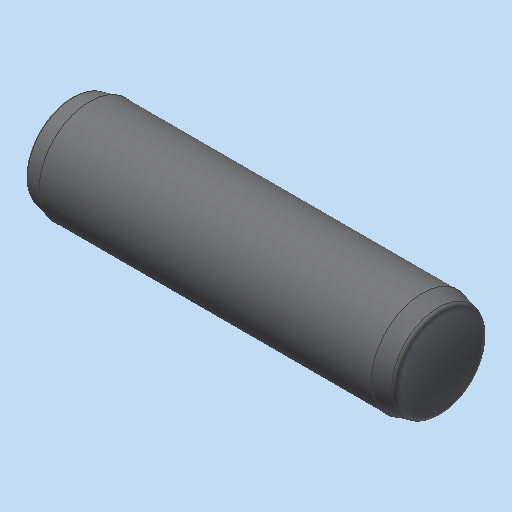
# Autodesk Inventor part: Zylinderstift_DIN_EN_ISO_8734___6x22
Saved by Autodesk Inventor 2023.3 (Build 273359000, 359)
## iProperties
Shininess: 64.0
Length Units: 11269
Angle Units: 11279
Time Units: 11290
Mass Units: 11283
Length Display Precision: 3
Angle Display Precision: 2
Compacted: True
Part Number: Zylinderstift_DIN_EN_ISO_8734___6x22
Document SubType Name: Modeling
Created: 2004-04-23
Description: =<RBPARTNOTITLE2>
Vendor: NORM8
Designer: C.Fischer
Manufacturer: Standard
Standards Organization: Custom
Density: 7.85 g/cm^3
Material: xStahl_AnP_Dummymaterial
Appearance: Stahl - normal AnP
Mass: 4.7383 g
Surface Area: 4.56133 cm^2
Volume: 0.603605 cm^3
DOC_ID: 5 F45 Zylinderstift_DIN_EN_ISO_8734___6x22
Control State: 0
Master: False
Checked Out: False
CNS_NB: Zylinderstift DIN EN ISO 8734 - 6x22
CNS_NN: DIN EN ISO 8734
CNS_NT: Zylinderstifte, aus gehaertetem Stahl und martensitischem nichtrostendem Stahl
CNS_NBSYN: Zylinderstift DIN EN ISO 8734 - $NENN.
CNS_LINA: Zylinderstift DIN EN ISO 8734 - 6x22
CNS_D: 6.000
CNS_L: 22.000
CNS_A: 1.200
CNS_NENN: 6x22
CNS_KT: DUMMY
PSOL_IDENT_0: {C:\partsolutions\data\23d-libs\bosch_bamberg\stifte\scherstifte\din_en_iso_8734.prj},164 {VTYP=3D},
PSOL_IDENT_1: {NB=Zylinderstift DIN EN ISO 8734 - 6x22},{NN=DIN EN ISO 8734},{DATE=26.11.2003},{GEOMDATE=26.11.200
PSOL_IDENT_2: 3},{VERSION=v1},{LINEID=790},{LINESUBID=-1},{WBVAR=}  {NB=Zylinderstift DIN EN ISO 8734 - 6x22},{LIN
PSOL_IDENT_3: A=Zylinderstift DIN EN ISO 8734 - 6x22},{KT=DUMMY},{IDNR=},{D=6.000},{L=22.000},{A=1.200},{NENN=6x22
PSOL_IDENT_4: }
DEF_STKID: T19045
Bezeichnung1: Zylinderstift DIN EN ISO 8734 - 6x22
Bezeichnung2: Zylinderstifte, aus gehaertetem Stahl u
RBPARTNOTITLE1: Parallel pins of hardened and martensitic stainless steel
RBPARTNOTITLE2: Zylinderstifte, aus gehaertetem Stahl und martensitischem nichtrostendem Stahl
RBDRAWINGMISSINGSPEC: --
AnP_Kategorie: 5
RBPARTMADEOF: ISO 8734 - 6x22 - A - St
Density: 0.0
Volumn: 0.0
Area: 0.0
PropertySet Name: Model Information
Title: Zylinderstift DIN EN ISO 8734 - 6x22
Author: C.Fischer
Keywords: =<RBPARTMADEOF>
Comments: =<RBSURFACE2>
Revision Number: 01
Autodesk Inventor part; units mm, degrees
sketch "Sketch_1" plane through (0, 0, 0) normal (0, 0, 1) x (1, 0, 0)
  line L0 (22, 0) -> (0, 0)
  arc A0 (0.48, 0) -> (0.0846, 2.4378) centre (-7.2331, 0) ccw
  arc A1 (0.2502, 2.7455) -> (0.0846, 2.4378) centre (0.3123, 2.5137) ccw
  line L1 (0.2502, 2.7455) -> (1.2, 3)
  line L2 (1.2, 3) -> (20.8, 3)
  line L3 (20.8, 3) -> (21.7498, 2.7455)
  arc A2 (21.9154, 2.4378) -> (21.7498, 2.7455) centre (21.6877, 2.5137) ccw
  arc A3 (21.9154, 2.4378) -> (21.52, 0) centre (29.2331, 0) ccw
  line L4 (21.52, 0) -> (0.48, 0)
  constraints: 10 end point, 8 point on circle, 4 centre point
revolve "Revolution1" add sketch "Sketch_1" angle 360 about axis through (22, 0, 0) along (1, 0, 0)
ref_plane "IP2_XY" through (0, 0, 0) normal (1, 0, 0) x (0, 0, -1)
ref_plane "IP2_YZ" through (0, 0, 0) normal (0, 0, -1) x (0, 1, 0)
ref_plane "IP1_XY" through (11, 0, 0) normal (1, 0, 0) x (0, 0, -1)
ref_plane "IP1_YZ" through (11, 0, 0) normal (0, 0, -1) x (0, 1, 0)
ref_plane "IP3_XY" through (22, 0, 0) normal (1, 0, 0) x (0, 0, -1)
ref_plane "IP3_YZ" through (22, 0, 0) normal (0, 0, -1) x (0, 1, 0)
